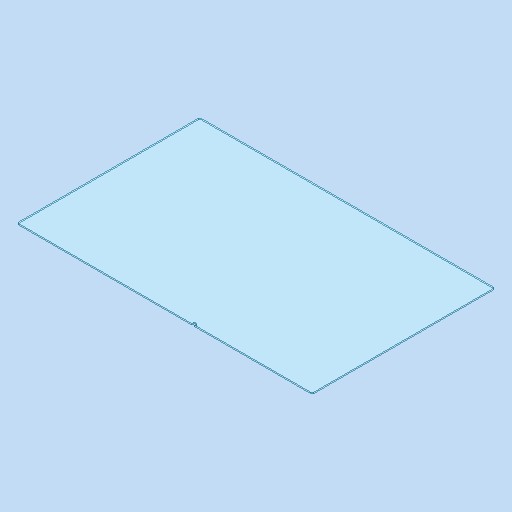
# Autodesk Inventor part: MM0861AN200_G22_152
Saved by Autodesk Inventor 2023.3 (Build 273359000, 359)
## iProperties
RuleStatus: InUse
Part Number: MM0861AN200_G22_152
Material: Kst - PC (Eslon, klar)
Description: =<RBPARTNOTITLE2>
Document SubType Name: Modeling
Designer: Benutzer
Mass: 2645.67 g
Surface Area: 11146 cm^2
Volume: 2204.72 cm^3
Density: 1.2 g/cm^3
Appearance: Klar AnP
Vendor: Koenig
RBDOCUMENTTYPE: DRF
RBDOCUMENTVERSION: 00
RBDRAWINGMAINSCALE: 1:1
RBDRAWINGMISSINGSPEC: --
RBDRAWINGVOLUME: --
RBGBEDGESIN1: +0,5
RBGBEDGESIN2: +0,2
RBGBEDGESOUT1: -0,3
RBGBEDGESOUT2: -0,1
RBMATERIAL: =<Material>
RBMATMEETS: --
RBMATNO: =<Part Number>
RBPARTMADEOF: 4 x 584 x 944 (FM)
RBPARTNO: SIEHE MNR
RBPARTNOTITLE1: manufactured part
RBPARTNOTITLE2: Anfertigungsteil
RBPARTSAFETYINDICATOR: --
RBSURFACE: --
RBSURFACE2: --
RBZEDGESNORM: ISO13715:2002-06
RBZGENDIMCLASS: m
RBZGENDIMNORM: ISO 2768-1:1989-11
RBZGENGEOCLASS: H
RBZGENGEONORM: ISO 2768-2:1989-11
RBZSURFACENORM: ISO13D2:2002-02
RBZTOLERANCENORM: ISO 14405-1:2010-12
AnP_Material: =<Material>
AnP_TemplVers: 20190222
AnP_Kategorie: 1
MaxAbmaße: 4 x 584 x 944 (FM)
Author: Benutzer
Keywords: =<RBPARTMADEOF>
Comments: =<RBSURFACE2>
Revision Number: 01
Autodesk Inventor part; units mm, degrees
ref_plane "YZ Plane" through (0, 0, 0) normal (1, 0, 0) x (0, 1, 0)
ref_plane "XZ Plane" through (0, 0, 0) normal (0, 1, 0) x (-1, 0, 0)
ref_plane "XY Plane" through (0, 0, 0) normal (0, 0, 1) x (1, 0, 0)
sketch "Skizze1" plane through (0, 0, 0) normal (0, 0, 1) x (1, 0, 0)
  line L0 (0, 0) -> (944, 0)
  line L1 (944, 0) -> (944, 584)
  line L2 (944, 584) -> (0, 584)
  line L3 (0, 584) -> (0, 0)
  dimension "d0" = 944
  dimension "d1" = 584
  constraints: 8 end point, 2 parallel, 1 horizontal, 1 perpendicular
  measures "d0" distance of L2.end L1.end
  measures "d1" distance between parallel lines of L0 L2
extrude "Extrusion1" add sketch "Skizze1" along normal blind 4
chamfer "Fase1" distance 5 angle 45 4 edges at (0, 0, 2) (944, 0, 2) (944, 584, 2) (0, 584, 2)
sketch "Skizze2" plane through (0, 0, 4) normal (0, 0, 1) x (1, 0, 0)
  line L0 (0, 579) -> (5, 584) projected
  line L1 (0, 579) -> (0, 5) projected
  line L2 (5, 0) -> (0, 5) projected
  line L3 (5, 0) -> (939, 0) projected
  line L4 (944, 5) -> (939, 0) projected
  line L5 (944, 5) -> (944, 579) projected
  line L6 (939, 584) -> (944, 579) projected
  line L7 (939, 584) -> (5, 584) projected
  line L8 (563, -5) -> (563, 5) construction
  line L9 (567, -5) -> (567, 5)
  line L10 (559, 5) -> (559, -5)
  arc A0 (559, -5) -> (567, -5) centre (563, -5) ccw
  arc A1 (567, 5) -> (559, 5) centre (563, 5) ccw
  point P0 (0, 0)
  point P1 (563, 0)
  dimension "d7" = 8
  dimension "d12" = 5
  dimension "d13" = 381
  constraints: 8 end point, 4 point on circle, 4 tangent, 2 centre point, 1 midpoint, 1 parallel, 1 perpendicular, 1 point on line
  measures "d7" diameter of A1
  measures "d12" distance from line of L3 L8.end
  measures "d13" distance from line of L5 L8.end
extrude "Extrusion2" cut sketch "Skizze2" against normal blind 10 contours L10 A1 L9 L3 | L3 L9 A0 L10
